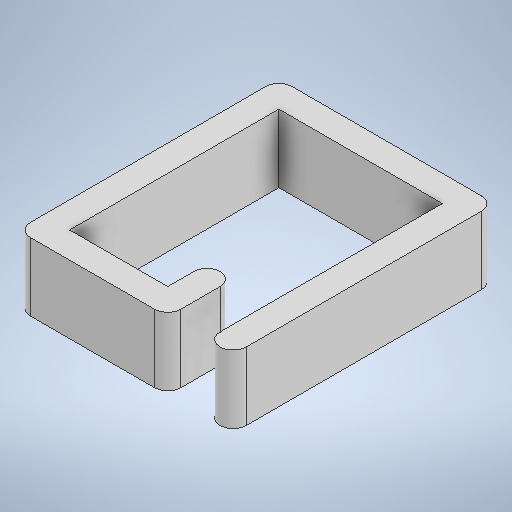
# Autodesk Inventor part: Sujeta_Cables
Saved by Autodesk Inventor 2025.3 (Build 293356030, 356C)
## iProperties
Created: 2026-05-06
Part Number: Sujeta_Cables
Material: Generic
Document SubType Name: Modeling
Designer: pablo
Density: 1 g/cm^3
Appearance: Default
Author: pablo
Autodesk Inventor part; units mm, degrees
ref_plane "YZ Plane" through (0, 0, 0) normal (1, 0, 0) x (0, 1, 0)
ref_plane "XZ Plane" through (0, 0, 0) normal (0, 1, 0) x (-1, 0, 0)
ref_plane "XY Plane" through (0, 0, 0) normal (0, 0, 1) x (1, 0, 0)
sketch "Sketch1" plane through (0, 0, 0) normal (0, 1, 0) x (-1, 0, 0)
  line L0 (0, 0) -> (2, 0)
  line L1 (2, 0) -> (2, -20)
  line L2 (2, -20) -> (0, -20)
  line L3 (0, -20) -> (0, 0)
  line L4 (2, -18) -> (16.5, -18)
  line L5 (16.5, -18) -> (16.5, -20)
  line L6 (16.5, -20) -> (2, -20)
  line L7 (2, -20) -> (2, -18)
  line L8 (14.5, -18) -> (16.5, -18)
  line L9 (16.5, -18) -> (16.5, 0)
  line L10 (16.5, 0) -> (14.5, 0)
  line L11 (14.5, 0) -> (14.5, -18)
  line L12 (14.5, 0) -> (5, 0)
  line L13 (5, 0) -> (5, -2)
  line L14 (5, -2) -> (14.5, -2)
  line L15 (14.5, -2) -> (14.5, 0)
  line L16 (5, -2) -> (7, -2)
  line L17 (7, -2) -> (7, -5)
  line L18 (7, -5) -> (5, -5)
  line L19 (5, -5) -> (5, -2)
  point P0 (15.5, 0)
  point P1 (1, 0)
  dimension "d0" = 20
  dimension "d1" = 2
  dimension "d2" = 14.5
  dimension "d3" = 11.5
  dimension "d4" = 3
  constraints: 40 end point, 10 parallel, 5 horizontal, 5 perpendicular, 4 equal length, 4 point on line, 2 midpoint, 1 horizontal alignment
  measures "d0" distance of L2.end L0.start
  measures "d1" distance of L0.start L0.end
  measures "d2" distance of L5.end L6.end
  measures "d3" distance between parallel lines of L9 L13
  measures "d4" distance of L18.end L13.end
extrude "Extrusion1" add sketch "Sketch1" along normal blind 5.2
fillet "Fillet1" radius 1 8 edges at (0, 2.6, 0) (-2, 2.6, 0) (0, 2.6, -20) (-16.5, 2.6, -20) (-16.5, 2.6, 0) (-5, 2.6, 0) (-5, 2.6, -5) (-7, 2.6, -5)
body "Solid1"
